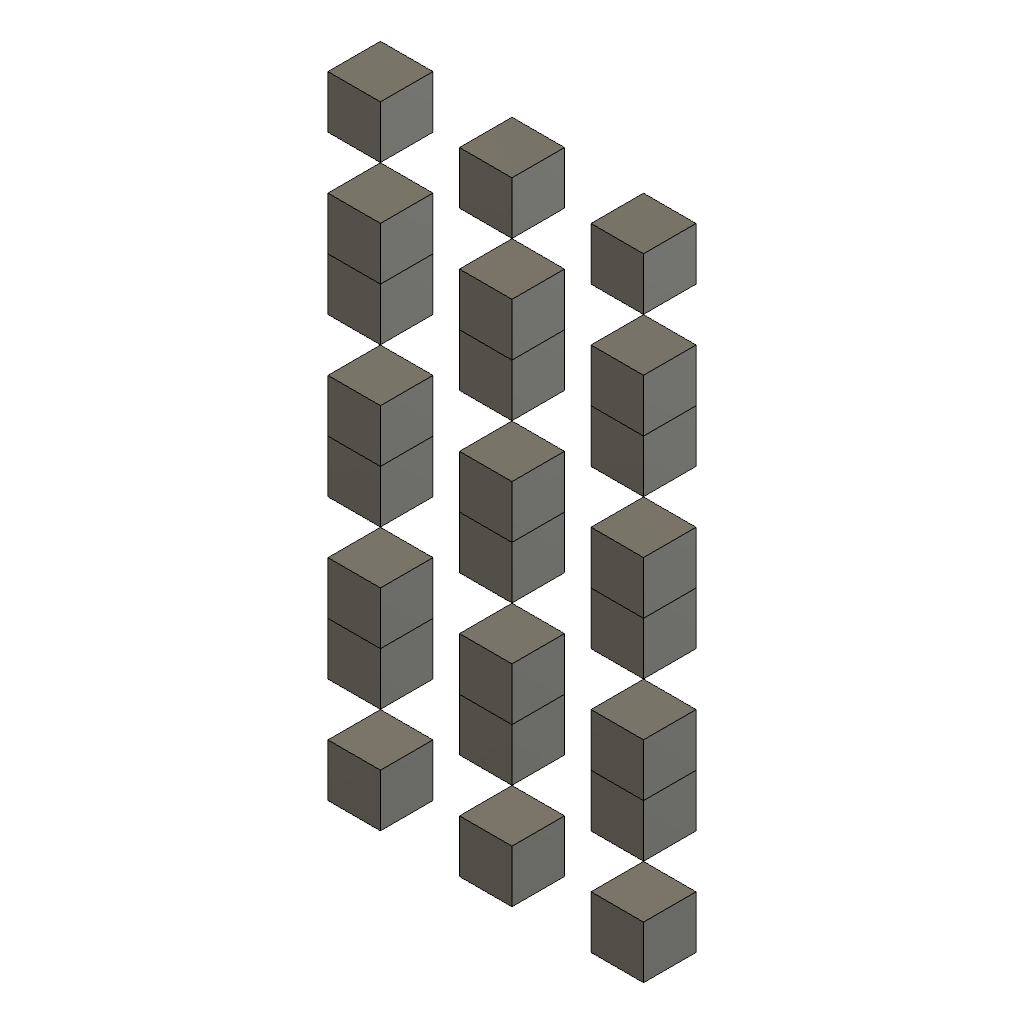
MultipleBodiesHistory (Autodesk Fusion 360 design; units mm, degrees)
part number: 2026-10-20-22-13-27-485
Autodesk Fusion 360 part; units mm, degrees
sketch "Sketch1" plane through (0, 0, 0) normal (0, 0, 1) x (1, 0, 0)
  line L0 (10, 0) -> (20, 0)
  line L1 (20, 0) -> (20, 10)
  line L2 (20, 10) -> (10, 10)
  line L3 (10, 10) -> (10, 0)
extrude "SeedFeature0" add sketch "Sketch1" along normal blind 10 makes body 1
sketch "Sketch2" plane through (0, 0, 0) normal (0, 0, 1) x (1, 0, 0)
  line L0 (10, 20) -> (20, 20)
  line L1 (20, 20) -> (20, 30)
  line L2 (20, 30) -> (10, 30)
  line L3 (10, 30) -> (10, 20)
extrude "SeedFeature1" add sketch "Sketch2" along normal blind 10 separate body makes body 2
pattern_linear "ProbeRectangularSymmetryHoldout" count 3 spacing 25 along (1, 0, 0) both ways count 4 spacing 30 along (0, 1, 0) both ways of bodies 1 2 makes body 3 at (-15, -23.3333, 3.3333) makes body 4 at (10, -23.3333, 3.3333) makes body 5 at (35, -23.3333, 3.3333) makes body 6 at (-15, 6.6667, 3.3333) makes body 7 at (35, 6.6667, 3.3333) makes body 8 at (-15, 36.6667, 3.3333) makes body 9 at (10, 36.6667, 3.3333) makes body 10 at (35, 36.6667, 3.3333) makes body 11 at (-15, 66.6667, 3.3333) makes body 12 at (10, 66.6667, 3.3333) makes body 13 at (35, 66.6667, 3.3333) makes body 14 at (-15, -3.3333, 3.3333) makes body 15 at (10, -3.3333, 3.3333) makes body 16 at (35, -3.3333, 3.3333) makes body 17 at (-15, 26.6667, 3.3333) makes body 18 at (35, 26.6667, 3.3333) makes body 19 at (-15, 56.6667, 3.3333) makes body 20 at (10, 56.6667, 3.3333) makes body 21 at (35, 56.6667, 3.3333) makes body 22 at (-15, 86.6667, 3.3333) makes body 23 at (10, 86.6667, 3.3333) makes body 24 at (35, 86.6667, 3.3333)
named bodies: "SeedBody0", "SeedBody1", "SeedBody0 (1)", "SeedBody0 (2)", "SeedBody0 (3)", "SeedBody0 (4)", "SeedBody0 (5)", "SeedBody0 (6)", "SeedBody0 (7)", "SeedBody0 (8)", "SeedBody0 (9)", "SeedBody0 (10)", "SeedBody0 (11)", "SeedBody1 (1)", "SeedBody1 (2)", "SeedBody1 (3)", "SeedBody1 (4)", "SeedBody1 (5)", "SeedBody1 (6)", "SeedBody1 (7)", "SeedBody1 (8)", "SeedBody1 (9)", "SeedBody1 (10)", "SeedBody1 (11)"
